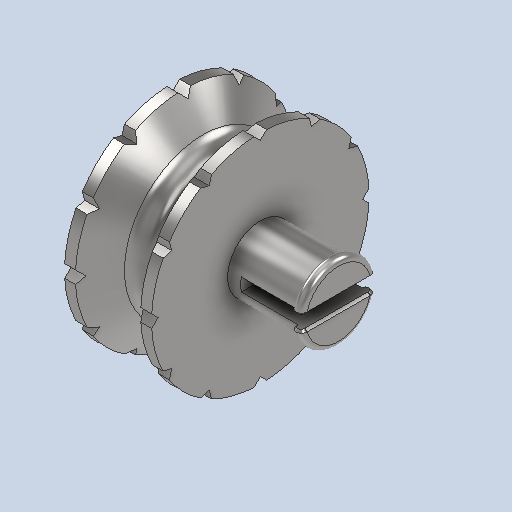
# Autodesk Inventor part: pulley
Saved by Autodesk Inventor 2026.1 (Build 301233020, 233B)
## iProperties
Created: 2025-11-30
Part Number: pulley
Material: Acciaio, Carbonio
Document SubType Name: Modeling
Designer: maxbu
Density: 7.85 g/cm^3
Appearance: Semilucidato
Mass: 1.92212 g
Surface Area: 3.37878 cm^2
Volume: 0.244856 cm^3
Author: maxbu
Autodesk Inventor part; units mm, degrees
ref_plane "YZ Plane" through (0, 0, 0) normal (1, 0, 0) x (0, 1, 0)
ref_plane "XZ Plane" through (0, 0, 0) normal (0, 1, 0) x (-1, 0, 0)
ref_plane "XY Plane" through (0, 0, 0) normal (0, 0, 1) x (1, 0, 0)
sketch "Schizzo1" plane through (0, 0, 0) normal (0, 1, 0) x (-1, 0, 0)
  line L0 (0, 0) -> (0, -4)
  line L1 (-4, -4) -> (-4, -1.5)
  line L2 (-4, -1.5) -> (-7, -1.5)
  line L3 (-7, -1.5) -> (-7, 0)
  line L4 (-7, 0) -> (0, 0)
  arc A0 (-1.3621, -3.6056) -> (-2.6379, -3.6056) centre (-2, -4) ccw
  line L5 (-0.5, -5) -> (0, -5)
  line L6 (0, -5) -> (0, -4)
  line L7 (-0.5, -5) -> (-1.3621, -3.6056)
  line L8 (-2, -4) -> (-2, 0) construction
  line L9 (-3.5, -5) -> (-4, -5)
  line L10 (-4, -5) -> (-4, -4)
  line L11 (-3.5, -5) -> (-2.6379, -3.6056)
  dimension "d8" = 4
  dimension "d11" = 3
  dimension "d14" = 4
  dimension "d16" = 1.5
  dimension "d18" = 1.5
  dimension "d19" = 4
  dimension "d31" = 5
  dimension "d32" = 0.5
  dimension "d33" = 2
  constraints: 24 end point, 5 vertical, 3 horizontal, 3 symmetric about line, 2 point on circle, 1 centre point, 1 coincident, 1 perpendicular, 1 point on line, 1 tangent
  measures "d8" distance of L0.end L1.start
  measures "d11" distance of L1.end L2.end
  measures "d14" distance of L0.start L0.end
  measures "d16" distance between parallel lines of L4 L2
  measures "d18" diameter of A0
  measures "d19" distance from line of L4 L8.start
  measures "d31" distance of L5.end point (0, 0)
  measures "d32" distance of L5.start L5.end
  measures "d33" distance between parallel lines of L1 L8
revolve "Rivoluzione1" add sketch "Schizzo1" angle 360 about axis through (7, 0, 0) along (-1, 0, 0)
sketch "Schizzo2" plane through (0, 0, 0) normal (1, 0, 0) x (0, 1, 0)
  line L0 (0, 0) -> (0, -5) construction
  line L1 (0, -5) -> (0.3, -5)
  line L2 (0, -5) -> (-0.3, -5)
  line L3 (-0.3, -5) -> (0, -4.7)
  line L4 (0, -4.7) -> (0.3, -5)
  dimension "d23" = 0.3
  dimension "d24" = 0.3
  dimension "d25" = 5
  constraints: 10 end point, 2 horizontal, 1 collinear, 1 point on line, 1 vertical
  measures "d23" distance of L0.end L1.end
  measures "d24" horizontal distance of L3.end L1.end
  measures "d25" distance of L0.start L0.end
extrude "Estrusione1" cut sketch "Schizzo2" along normal blind 10
pattern_circular "Serie circolare1" count 12 over 360 about axis through (0.25, 0, 0) along (-1, 0, 0) of "Estrusione1"
sketch "Schizzo3" plane through (0, 0, 0) normal (0, 1, 0) x (-1, 0, 0)
  line L0 (-7, -1.5) -> (-7, 1.5) projected
  line L1 (-7, -1.5) -> (-7.1, -1.5)
  line L2 (-7.1, -1.5) -> (-7.1, -1.5)
  line L3 (-7.35, -1.75) -> (-7.35, -1.75)
  line L4 (-7.6, -1.5) -> (-7.6, 0)
  line L5 (-7.6, 0) -> (-7, 0)
  arc A0 (-7.35, -1.75) -> (-7.1, -1.5) centre (-7.35, -1.5) ccw
  arc A1 (-7.6, -1.5) -> (-7.35, -1.75) centre (-7.35, -1.5) ccw
  point P0 (0, 0)
  point P1 (-7.1, -1.75)
  point P2 (-7.6, -1.75)
  dimension "d34" = 0.1
  dimension "d35" = 0.5
  dimension "d36" = 0.25
  dimension "d37" = 0.25
  constraints: 10 end point, 4 point on circle, 4 point on line, 4 tangent, 3 perpendicular, 2 centre point, 2 horizontal, 1 concentric, 1 midpoint
  measures "d34" distance of L0.start L1.end
  measures "d35" distance of point (-7.1, -1.75) point (-7.6, -1.75)
  measures "d36" distance of L1.end point (-7.1, -1.75)
  measures "d37" radius of A0
revolve "Rivoluzione2" add sketch "Schizzo3" angle 360 about axis through (7.6, 0, 0) along (-1, 0, 0)
sketch "Schizzo4" plane through (7.6, 0, 0) normal (1, 0, 0) x (0, 0, -1)
  line L0 (-2.5, 0.3) -> (2.5, 0.3)
  line L1 (2.5, 0.3) -> (2.5, -0.3)
  line L2 (2.5, -0.3) -> (-2.5, -0.3)
  line L3 (-2.5, -0.3) -> (-2.5, 0.3)
  line L4 (-2.5, 0.3) -> (2.5, -0.3) construction
  line L5 (2.5, 0.3) -> (-2.5, -0.3) construction
  point P0 (0, 0)
  dimension "d39" = 0.6
  dimension "d40" = 5
  constraints: 12 end point, 2 midpoint, 2 parallel, 1 horizontal, 1 perpendicular
  measures "d39" distance of L0.end L1.end
  measures "d40" distance of L1.end L2.end
extrude "Estrusione2" cut sketch "Schizzo4" against normal blind 3
chamfer "Smusso2" distance 0.1 angle 45 6 edges at (7.6, 0.3, 0) (7.1732, 0.3, 1.6496) (7.1732, 0.3, -1.6496) (7.6, -0.3, 0) (7.1732, -0.3, -1.6496) (7.1732, -0.3, 1.6496)
